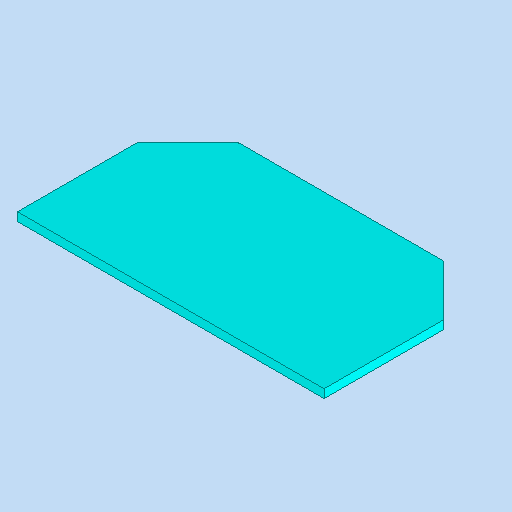
# Autodesk Inventor part: MM09484AN130_G02_102
Saved by Autodesk Inventor 2023.3 (Build 273359000, 359)
## iProperties
Created: 2023-06-22
Part Number: MM09484AN130_G02_102
Material: Generisch
Description: =<RBPARTNOTITLE2>
Document SubType Name: Modeling
Designer: RIC7AN
Mass: 0.7524 g
Surface Area: 3.68243 cm^2
Volume: 0.0855 cm^3
Density: 8.8 g/cm^3
Appearance: türkis AnP
Vendor: Sick
RBPARTMADEOF: REF-AC
RBDRAWINGMISSINGSPEC: --
AnP_Kategorie: 2
RBPARTNOTITLE2: Reflektorfolie
RBSURFACE: --
RBPARTNOTITLE1: reflection foil
AnP_Material: =<Material>
RBMATERIAL: --
RBMATNO: =<Part Number>
RBPARTNO: SIEHE MNR
Author: RIC7AN
Keywords: =<RBPARTMADEOF>
Comments: =<RBSURFACE2>
Revision Number: 01
Autodesk Inventor part; units mm, degrees
ref_plane "YZ Plane" through (0, 0, 0) normal (1, 0, 0) x (0, 1, 0)
ref_plane "XZ Plane" through (0, 0, 0) normal (0, 1, 0) x (-1, 0, 0)
ref_plane "XY Plane" through (0, 0, 0) normal (0, 0, 1) x (1, 0, 0)
sketch "Skizze1" plane through (0, 0, 0) normal (0, 0, 1) x (1, 0, 0)
  line L0 (-9, 5) -> (9, 5)
  line L1 (9, 5) -> (9, -5)
  line L2 (9, -5) -> (-9, -5)
  line L3 (-9, -5) -> (-9, 5)
  line L4 (0, 7) -> (0, -7) projected
  line L5 (-12.6, 0) -> (12.6, 0) projected
  point P0 (0, 0)
  dimension "d0" = 18
  dimension "d1" = 10
  constraints: 8 end point, 2 parallel, 1 horizontal, 1 perpendicular, 2 other
  measures "d0" distance of L0.start L0.end
  measures "d1" distance of L0.end L1.end
extrude "Extrusion1" add sketch "Skizze1" along normal blind 0.5
chamfer "Fase1" distance 3 angle 45 2 edges at (-9, 5, 0.25) (9, 5, 0.25)
